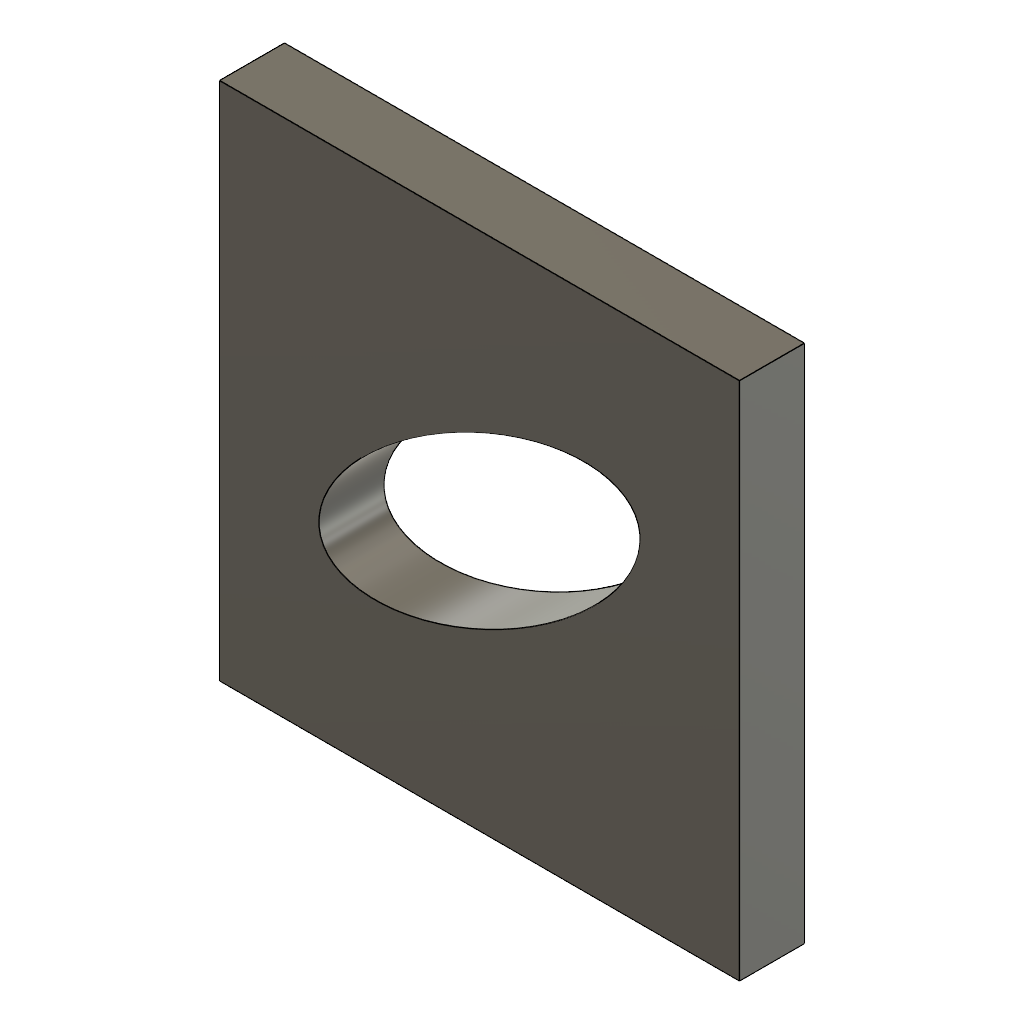
sk_ellipse_rotated_cut (Autodesk Fusion 360 design; units mm, degrees)
part number: 2026-11-13-14-35-23-160
Autodesk Fusion 360 part; units mm, degrees
sketch "Sketch1" plane through (0, 0, 0) normal (0, 0, 1) x (1, 0, 0)
  line L0 (-20, -20) -> (20, -20)
  line L1 (20, -20) -> (20, 20)
  line L2 (20, 20) -> (-20, 20)
  line L3 (-20, 20) -> (-20, -20)
extrude "Extrude1" add sketch "Sketch1" along normal blind 5
sketch "Sketch2" plane through (0, 0, 0) normal (0, 0, 1) x (1, 0, 0)
  ellipse E0 centre (0, 0) end of major axis (12, 7) minor radius 5.8306
  line L0 (-12, -7) -> (12, 7) construction
  line L1 (-2.9379, 5.0363) -> (2.9379, -5.0363) construction
  constraint coincident E0 L0.start
  constraint coincident E0 L0.end
  constraint coincident E0 L1.start
  constraint coincident E0 L1.end
extrude "Extrude2" cut sketch "Sketch2" along normal through all
